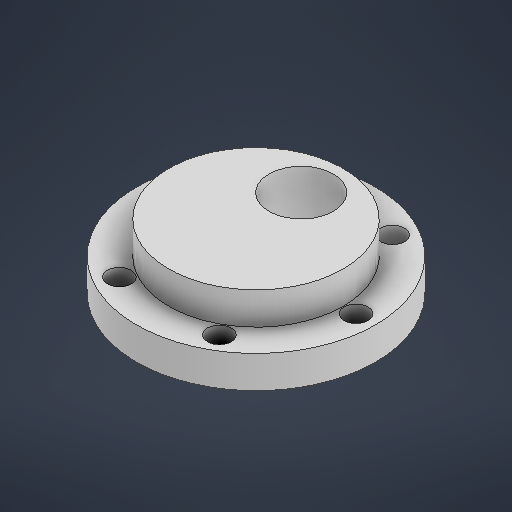
# Autodesk Inventor part: Adaptateur_Roulements_AxeRoues
Saved by Autodesk Inventor 2026 (Build 300175000, 175)
## iProperties
Created: 2025-05-11
Part Number: Adaptateur_Roulements_AxeRoues
Material: Générique
Document SubType Name: Modeling
Designer: Diogo
Density: 1 g/cm^3
Appearance: Par défaut
Author: Diogo
Autodesk Inventor part; units mm, degrees
ref_plane "YZ Plane" through (0, 0, 0) normal (1, 0, 0) x (0, 1, 0)
ref_plane "XZ Plane" through (0, 0, 0) normal (0, 1, 0) x (-1, 0, 0)
ref_plane "XY Plane" through (0, 0, 0) normal (0, 0, 1) x (1, 0, 0)
sketch "Esquisse1" plane through (0, 0, 0) normal (0, 0, 1) x (1, 0, 0)
  line L0 (0, 0) -> (0, 10)
  line L1 (0, 10) -> (13.5, 10)
  line L2 (13.5, 10) -> (13.5, 5)
  line L3 (0, 0) -> (18.5, 0)
  line L4 (18.5, 0) -> (18.5, 5)
  line L5 (18.5, 5) -> (13.5, 5)
  line L6 (0, 51.6158) -> (0, -25.6735)
  dimension "d0" = 10
  dimension "d1" = 13.5
  dimension "d2" = 5
  dimension "d3" = 18.5
  dimension "d4" = 5
  constraints: 14 end point, 3 vertical, 2 perpendicular, 1 horizontal
  measures "d0" distance of L0.start L0.end
  measures "d1" distance of L0.end L1.end
  measures "d2" distance of L1.end L2.end
  measures "d3" distance of L0.start L3.end
  measures "d4" distance of L3.end L4.end
revolve "Révolution1" add sketch "Esquisse1" angle 360 about axis through (0, 51.6158, 0) along (0, -1, 0)
sketch "Esquisse2" plane through (0, 5, 0) normal (0, 1, 0) x (1, 0, 0)
  circle A0 centre (-15.5, 0) radius 1.85
  circle A1 centre (0, 0) radius 15.5 construction
  circle A2 centre (0, 7) radius 5
  circle A3 centre (-7.75, -13.4234) radius 1.85
  circle A4 centre (7.75, -13.4234) radius 1.85
  circle A5 centre (15.5, 0) radius 1.85
  circle A6 centre (7.75, 13.4234) radius 1.85
  circle A7 centre (-7.75, 13.4234) radius 1.85
  dimension "d7" = 31
  dimension "d6" = 3.7
  dimension "d8" = 10
  dimension "d9" = 7
  dimension "d12" = 360
  constraints: 7 centre point, 1 coincident, 1 horizontal alignment, 15 other
  measures "d6" diameter of A0
  measures "d8" diameter of A2
  measures "d9" distance of A2.centre point (0, 0)
extrude "Extrusion1" cut sketch "Esquisse2" along normal through all both and the other way through all
